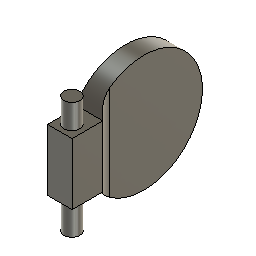
closing element (Autodesk Fusion 360 design; units mm, degrees)
part number: 2026-03-27-16-31-58-847
Autodesk Fusion 360 part; units mm, degrees
sketch "Sketch1" plane through (0, 0, 0) normal (1, 0, 0) x (0, 1, 0)
  circle A0 centre (0, 0) radius 9.5
  dimension "d1" = 19
  constraint coincident A0.centre origin
  measures "d1" diameter of A0
extrude "Extrude1" add sketch "Sketch1" along normal blind 3
sketch "Sketch2" plane through (3, 0, 0) normal (1, 0, 0) x (0, 1, 0)
  circle A0 centre (0, 0) radius 9.5
  line L0 (-8.0777, 5) -> (-13.0777, 5)
  line L1 (-13.0777, 5) -> (-13.0777, -5)
  line L2 (-13.0777, -5) -> (-8.0777, -5)
  line L3 (-8.0777, -5) -> (-8.0777, 5)
  dimension "d4" = 5
  dimension "d5" = 10
  constraint horizontal L0
  constraint vertical L1
  constraint horizontal L2
  constraint vertical L3
  constraint coincident A0 L0.start
  constraint coincident A0 L2.end
  measures "d4" distance of L0.start L0.end
  measures "d5" distance of L0.start L2.end
extrude "Extrude2" add sketch "Sketch2" along normal blind 1 contours A0 L3 | A0 L0 L1 L2 picked at (-8.2821, 1.2788)
extrude "Extrude3" add 1 faces at (3, -11.8852, 0) along direction (-1, 0, 0) blind 2.6
extrude "Extrude4" add 1 faces at (4, -11.4111, 1.6667) along direction (1, 0, 0) blind 0.4
sketch "Sketch3" plane through (0, 0, -5) normal (0, 0, -1) x (1, 0, 0)
  line L0 (3, 8.0777) -> (4.4, 8.0777)
  line L1 (4.4, 8.0777) -> (4.4, 13.0777)
  line L2 (4.4, 13.0777) -> (0.4, 13.0777)
  line L3 (0.4, 13.0777) -> (0.4, 8.0777)
  line L4 (0.4, 8.0777) -> (3, 8.0777)
  line L5 (4.4, 13.0777) -> (0.4, 13.0777)
  line L6 (0.4, 13.0777) -> (0.4, 8.0777)
  line L7 (0.4, 8.0777) -> (4.4, 8.0777)
  line L8 (4.4, 8.0777) -> (4.4, 13.0777)
  circle A0 centre (2.36, 11.0777) radius 1.3
  dimension "d12" = 2.6
  dimension "d21" = 2
  constraint horizontal L5
  constraint vertical L6
  constraint horizontal L7
  constraint vertical L8
  constraint coincident L3.end L4.start
  constraint coincident L1.end L2.start
  measures "d12" diameter of A0
  measures "d21" distance of L5 A0.centre
extrude "Extrude5" add sketch "Sketch3" along normal blind 5 and the other way blind 14 contours A0
fillet "Fillet1" radius 3 1 edges at (3, -8.0777, 0)
fillet "Fillet1" radius 1 1 edges at (0.4, -9.5, 0)
